Autodesk Fusion 360 part; units mm, degrees
(part 2 of 2)
sketch "Logo" plane through (0, 0, 0) normal (0, 1, 0) x (1, 0, 0)
  line L0 (160, 0) -> (201, 0)
  line L1 (201, 0) -> (201, 7)
  line L2 (201, 7) -> (160, 7)
  line L3 (160, 7) -> (160, 0)
  line L4 (196.0195, -0.004) -> (196.0195, 0.9966)
  line L5 (196.0195, 0.9966) -> (201.0223, 0.9966)
  line L6 (201.0223, 0.9966) -> (201.0223, -0.004)
  line L7 (201.0223, -0.004) -> (196.0195, -0.004)
  line L8 (196.0195, 6.9998) -> (201.0223, 6.9998)
  line L9 (201.0223, 6.9998) -> (201.0223, 5.9993)
  line L10 (201.0223, 5.9993) -> (196.0195, 5.9993)
  line L11 (196.0195, 5.9993) -> (196.0195, 6.9998)
  line L12 (191.0168, 0.9966) -> (194.0184, 0.9966)
  line L13 (194.0184, 0.9966) -> (194.0184, -0.004)
  line L14 (194.0184, -0.004) -> (191.0168, -0.004)
  line L15 (191.0168, -0.004) -> (191.0168, 0.9966)
  line L16 (190.0163, 5.9993) -> (191.0168, 5.9993)
  line L17 (191.0168, 5.9993) -> (191.0168, 0.9966)
  line L18 (191.0168, 0.9966) -> (190.0163, 0.9966)
  line L19 (190.0163, 0.9966) -> (190.0163, 5.9993)
  line L20 (194.0184, 6.9998) -> (194.0184, 5.9993)
  line L21 (194.0184, 5.9993) -> (191.0168, 5.9993)
  line L22 (191.0168, 5.9993) -> (191.0168, 6.9998)
  line L23 (191.0168, 6.9998) -> (194.0184, 6.9998)
  line L24 (186.0141, -0.004) -> (185.0135, -0.004)
  line L25 (185.0135, -0.004) -> (185.0135, 0.9966)
  line L26 (185.0135, 0.9966) -> (186.0141, 0.9966)
  line L27 (186.0141, 0.9966) -> (186.0141, 4.9987)
  line L28 (186.0141, 4.9987) -> (187.0146, 4.9987)
  line L29 (187.0146, 4.9987) -> (187.0146, 0.9966)
  line L30 (187.0146, 0.9966) -> (188.0152, 0.9966)
  line L31 (188.0152, 0.9966) -> (188.0152, -0.004)
  line L32 (188.0152, -0.004) -> (186.0141, -0.004)
  line L33 (185.0135, 6.9998) -> (188.0152, 6.9998)
  line L34 (188.0152, 6.9998) -> (188.0152, 5.9993)
  line L35 (188.0152, 5.9993) -> (185.0135, 5.9993)
  line L36 (185.0135, 5.9993) -> (185.0135, 6.9998)
  line L37 (179.0103, -0.004) -> (178.0097, -0.004)
  line L38 (178.0097, -0.004) -> (178.0097, 4.9987)
  line L39 (178.0097, 4.9987) -> (179.0103, 4.9987)
  line L40 (179.0103, 4.9987) -> (179.0103, 0.9966)
  line L41 (179.0103, 0.9966) -> (182.0119, 0.9966)
  line L42 (182.0119, 0.9966) -> (182.0119, -0.004)
  line L43 (182.0119, -0.004) -> (179.0103, -0.004)
  line L44 (182.0119, 5.9993) -> (183.0124, 5.9993)
  line L45 (183.0124, 5.9993) -> (183.0124, 0.9966)
  line L46 (183.0124, 0.9966) -> (182.0119, 0.9966)
  line L47 (182.0119, 0.9966) -> (182.0119, 5.9993)
  line L48 (178.0097, 6.9998) -> (182.0119, 6.9998)
  line L49 (182.0119, 6.9998) -> (182.0119, 5.9993)
  line L50 (182.0119, 5.9993) -> (178.0097, 5.9993)
  line L51 (178.0097, 5.9993) -> (178.0097, 6.9998)
  line L52 (172.0064, 0.9966) -> (177.0092, 0.9966)
  line L53 (177.0092, 0.9966) -> (177.0092, -0.004)
  line L54 (177.0092, -0.004) -> (172.0064, -0.004)
  line L55 (172.0064, -0.004) -> (172.0064, 0.9966)
  line L56 (170.0054, 4.9987) -> (171.0059, 4.9987)
  line L57 (171.0059, 4.9987) -> (171.0059, 0.9966)
  line L58 (171.0059, 0.9966) -> (170.0054, 0.9966)
  line L59 (170.0054, 0.9966) -> (170.0054, 4.9987)
  line L60 (170.0054, -0.004) -> (167.0037, -0.004)
  line L61 (167.0037, -0.004) -> (167.0037, 0.9966)
  line L62 (167.0037, 0.9966) -> (170.0054, 0.9966)
  line L63 (170.0054, 0.9966) -> (170.0054, -0.004)
  line L64 (166.0032, 0.9966) -> (166.0032, 4.9987)
  line L65 (166.0032, 4.9987) -> (167.0037, 4.9987)
  line L66 (167.0037, 4.9987) -> (167.0037, 0.9966)
  line L67 (167.0037, 0.9966) -> (166.0032, 0.9966)
  line L68 (167.0037, 5.9993) -> (170.0054, 5.9993)
  line L69 (170.0054, 5.9993) -> (170.0054, 4.9987)
  line L70 (170.0054, 4.9987) -> (167.0037, 4.9987)
  line L71 (167.0037, 4.9987) -> (167.0037, 5.9993)
  line L72 (164.0021, 4.9987) -> (165.0026, 4.9987)
  line L73 (165.0026, 4.9987) -> (165.0026, -0.004)
  line L74 (165.0026, -0.004) -> (164.0021, -0.004)
  line L75 (164.0021, -0.004) -> (164.0021, 4.9987)
  line L76 (161.0004, -0.004) -> (159.9999, -0.004)
  line L77 (159.9999, -0.004) -> (159.9999, 5.9993)
  line L78 (159.9999, 5.9993) -> (164.0021, 5.9993)
  line L79 (164.0021, 5.9993) -> (164.0021, 4.9987)
  line L80 (164.0021, 4.9987) -> (161.0004, 4.9987)
  line L81 (161.0004, 4.9987) -> (161.0004, -0.004)
  line L82 (200.0217, 2.9977) -> (196.0195, 2.9977)
  line L83 (196.0195, 2.9977) -> (196.0195, 3.9982)
  line L84 (196.0195, 3.9982) -> (200.0217, 3.9982)
  line L85 (200.0217, 3.9982) -> (200.0217, 2.9977)
  line L86 (160, 10) -> (180.5, 10)
  line L87 (180.5, 10) -> (180.5, 13.5)
  line L88 (180.5, 13.5) -> (160, 13.5)
  line L89 (160, 13.5) -> (160, 10)
  line L90 (177.9981, 9.9995) -> (177.9981, 10.4994)
  line L91 (177.9981, 10.4994) -> (180.4979, 10.4994)
  line L92 (180.4979, 10.4994) -> (180.4979, 9.9995)
  line L93 (180.4979, 9.9995) -> (177.9981, 9.9995)
  line L94 (177.9981, 13.4992) -> (180.4979, 13.4992)
  line L95 (180.4979, 13.4992) -> (180.4979, 12.9993)
  line L96 (180.4979, 12.9993) -> (177.9981, 12.9993)
  line L97 (177.9981, 12.9993) -> (177.9981, 13.4992)
  line L98 (175.4983, 10.4994) -> (176.9982, 10.4994)
  line L99 (176.9982, 10.4994) -> (176.9982, 9.9995)
  line L100 (176.9982, 9.9995) -> (175.4983, 9.9995)
  line L101 (175.4983, 9.9995) -> (175.4983, 10.4994)
  line L102 (174.9984, 12.9993) -> (175.4983, 12.9993)
  line L103 (175.4983, 12.9993) -> (175.4983, 10.4994)
  line L104 (175.4983, 10.4994) -> (174.9984, 10.4994)
  line L105 (174.9984, 10.4994) -> (174.9984, 12.9993)
  line L106 (176.9982, 13.4992) -> (176.9982, 12.9993)
  line L107 (176.9982, 12.9993) -> (175.4983, 12.9993)
  line L108 (175.4983, 12.9993) -> (175.4983, 13.4992)
  line L109 (175.4983, 13.4992) -> (176.9982, 13.4992)
  line L110 (172.9985, 9.9995) -> (172.4985, 9.9995)
  line L111 (172.4985, 9.9995) -> (172.4985, 10.4994)
  line L112 (172.4985, 10.4994) -> (172.9985, 10.4994)
  line L113 (172.9985, 10.4994) -> (172.9985, 12.4993)
  line L114 (172.9985, 12.4993) -> (173.4985, 12.4993)
  line L115 (173.4985, 12.4993) -> (173.4985, 10.4994)
  line L116 (173.4985, 10.4994) -> (173.9984, 10.4994)
  line L117 (173.9984, 10.4994) -> (173.9984, 9.9995)
  line L118 (173.9984, 9.9995) -> (172.9985, 9.9995)
  line L119 (172.4985, 13.4992) -> (173.9984, 13.4992)
  line L120 (173.9984, 13.4992) -> (173.9984, 12.9993)
  line L121 (173.9984, 12.9993) -> (172.4985, 12.9993)
  line L122 (172.4985, 12.9993) -> (172.4985, 13.4992)
  line L123 (169.4988, 9.9995) -> (168.9988, 9.9995)
  line L124 (168.9988, 9.9995) -> (168.9988, 12.4993)
  line L125 (168.9988, 12.4993) -> (169.4988, 12.4993)
  line L126 (169.4988, 12.4993) -> (169.4988, 10.4994)
  line L127 (169.4988, 10.4994) -> (170.9987, 10.4994)
  line L128 (170.9987, 10.4994) -> (170.9987, 9.9995)
  line L129 (170.9987, 9.9995) -> (169.4988, 9.9995)
  line L130 (170.9987, 12.9993) -> (171.4986, 12.9993)
  line L131 (171.4986, 12.9993) -> (171.4986, 10.4994)
  line L132 (171.4986, 10.4994) -> (170.9987, 10.4994)
  line L133 (170.9987, 10.4994) -> (170.9987, 12.9993)
  line L134 (168.9988, 13.4992) -> (170.9987, 13.4992)
  line L135 (170.9987, 13.4992) -> (170.9987, 12.9993)
  line L136 (170.9987, 12.9993) -> (168.9988, 12.9993)
  line L137 (168.9988, 12.9993) -> (168.9988, 13.4992)
  line L138 (165.999, 10.4994) -> (168.4988, 10.4994)
  line L139 (168.4988, 10.4994) -> (168.4988, 9.9995)
  line L140 (168.4988, 9.9995) -> (165.999, 9.9995)
  line L141 (165.999, 9.9995) -> (165.999, 10.4994)
  line L142 (164.9991, 12.4993) -> (165.4991, 12.4993)
  line L143 (165.4991, 12.4993) -> (165.4991, 10.4994)
  line L144 (165.4991, 10.4994) -> (164.9991, 10.4994)
  line L145 (164.9991, 10.4994) -> (164.9991, 12.4993)
  line L146 (164.9991, 9.9995) -> (163.4992, 9.9995)
  line L147 (163.4992, 9.9995) -> (163.4992, 10.4994)
  line L148 (163.4992, 10.4994) -> (164.9991, 10.4994)
  line L149 (164.9991, 10.4994) -> (164.9991, 9.9995)
  line L150 (162.9992, 10.4994) -> (162.9992, 12.4993)
  line L151 (162.9992, 12.4993) -> (163.4992, 12.4993)
  line L152 (163.4992, 12.4993) -> (163.4992, 10.4994)
  line L153 (163.4992, 10.4994) -> (162.9992, 10.4994)
  line L154 (163.4992, 12.9993) -> (164.9991, 12.9993)
  line L155 (164.9991, 12.9993) -> (164.9991, 12.4993)
  line L156 (164.9991, 12.4993) -> (163.4992, 12.4993)
  line L157 (163.4992, 12.4993) -> (163.4992, 12.9993)
  line L158 (161.9993, 12.4993) -> (162.4993, 12.4993)
  line L159 (162.4993, 12.4993) -> (162.4993, 9.9995)
  line L160 (162.4993, 9.9995) -> (161.9993, 9.9995)
  line L161 (161.9993, 9.9995) -> (161.9993, 12.4993)
  line L162 (160.4994, 9.9995) -> (159.9995, 9.9995)
  line L163 (159.9995, 9.9995) -> (159.9995, 12.9993)
  line L164 (159.9995, 12.9993) -> (161.9993, 12.9993)
  line L165 (161.9993, 12.9993) -> (161.9993, 12.4993)
  line L166 (161.9993, 12.4993) -> (160.4994, 12.4993)
  line L167 (160.4994, 12.4993) -> (160.4994, 9.9995)
  line L168 (179.998, 11.4994) -> (177.9981, 11.4994)
  line L169 (177.9981, 11.4994) -> (177.9981, 11.9993)
  line L170 (177.9981, 11.9993) -> (179.998, 11.9993)
  line L171 (179.998, 11.9993) -> (179.998, 11.4994)
  dimension "d388" = 41
  dimension "d389" = 7
  dimension "d390" = 20.5
  dimension "d391" = 3.5
  constraint horizontal L0
  constraint vertical L1
  constraint horizontal L2
  constraint vertical L3
  constraint horizontal L86
  constraint vertical L87
  constraint horizontal L88
  constraint vertical L89
  measures "d388" distance of L0.start L0.end
  measures "d389" distance of L0.start L2.end
  measures "d390" distance of L86.start L86.end
  measures "d391" distance of L86.start L88.end
extrude "Extrude42" add sketch "Logo" along normal blind 0.4 separate body contours L86 L89 L162 L163 L164 L165 L166 L167 | L86 L161 L166 L167 | L86 L88 L89 L124 L125 L126 L127 L133 L136 L137 L138 L139 L141 L142 L143 L144 L147 L149 L150 L151 L153 L154 L155 L157 L158 L159 L164 L165 | L86 L158 L159 L160 L161 | L88 L134 L135 L136 L137 | L86 L146 L147 L148 L149 | L86 L88 L101 L102 L104 L105 L108 L111 L112 L113 L114 L115 L116 L117 L120 L121 L122 L128 L130 L131 L132 L135 | L145 L148 L152 L156 | L150 L151 L152 L153 | L88 L119 L120 L121 L122 | L130 L131 L132 L133 | L86 L138 L139 L140 L141 | L142 L143 L144 L145 | L154 L155 L156 L157 | L86 L123 L124 L125 L126 L127 L128 L129 | L88 L106 L107 L108 L109 | L88 L94 L95 L96 L97 | L86 L87 L88 L90 L91 L92 L95 L96 L97 L98 L99 L103 L106 L107 | L102 L103 L104 L105 | L86 L110 L111 L112 L113 L114 L115 L116 L117 L118 | L86 L98 L99 L100 L101 | L86 L90 L91 L92 L93 | L168 L169 L170 L171 makes body 7
extrude "Extrude43" add sketch "Logo" along normal blind 1 contours L86 L89 L162 L163 L164 L165 L166 L167 | L86 L158 L159 L160 L161 | L88 L134 L135 L136 L137 | L86 L146 L147 L148 L149 | L150 L151 L152 L153 | L88 L119 L120 L121 L122 | L130 L131 L132 L133 | L86 L138 L139 L140 L141 | L142 L143 L144 L145 | L154 L155 L156 L157 | L86 L123 L124 L125 L126 L127 L128 L129 | L88 L106 L107 L108 L109 | L88 L94 L95 L96 L97 | L102 L103 L104 L105 | L86 L110 L111 L112 L113 L114 L115 L116 L117 L118 | L86 L98 L99 L100 L101 | L86 L90 L91 L92 L93 | L168 L169 L170 L171 bodies 7
extrude "Extrude44" add sketch "Side" along normal blind 2.8 contours L78 L79 L80 L81 bodies 6
sketch "Spacer" plane through (0, 0, 0) normal (0, 1, 0) x (1, 0, 0)
  line L0 (220, 0) -> (245.6, 0)
  line L1 (245.6, 0) -> (245.6, 19)
  line L2 (245.6, 19) -> (220, 19)
  line L3 (220, 19) -> (220, 0)
  line L4 (227.8, 0) -> (237.8, 0)
  line L5 (237.8, 0) -> (237.8, 10)
  line L6 (237.8, 10) -> (227.8, 10)
  line L7 (227.8, 10) -> (227.8, 0)
  line L8 (220.8, 0) -> (221.8, 0)
  line L9 (221.8, 0) -> (221.8, 19)
  line L10 (221.8, 19) -> (220.8, 19)
  line L11 (220.8, 19) -> (220.8, 0)
  line L12 (244.8, 0) -> (243.8, 0)
  line L13 (243.8, 0) -> (243.8, 19)
  line L14 (243.8, 19) -> (244.8, 19)
  line L15 (244.8, 19) -> (244.8, 0)
  dimension "d402" = 25.6
  dimension "d403" = 19
  dimension "d406" = 10
  dimension "d407" = 10
  dimension "d408" = 7.8
  dimension "d413" = 1
  dimension "d414" = 19
  dimension "d415" = 0.8
  dimension "d416" = 1
  dimension "d417" = 19
  dimension "d418" = 0.8
  constraint horizontal L0
  constraint vertical L1
  constraint horizontal L2
  constraint vertical L3
  constraint horizontal L4
  constraint vertical L5
  constraint horizontal L6
  constraint vertical L7
  constraint coincident L0 L4.start
  constraint horizontal L8
  constraint vertical L9
  constraint horizontal L10
  constraint vertical L11
  constraint coincident L0 L8.start
  constraint horizontal L12
  constraint vertical L13
  constraint horizontal L14
  constraint vertical L15
  constraint coincident L0 L12.start
  measures "d402" distance of L0.start L0.end
  measures "d403" distance of L0.start L2.end
  measures "d406" distance of L4.start L4.end
  measures "d407" distance of L4.start L6.end
  measures "d408" distance of L3 L7
  measures "d413" distance of L8.start L8.end
  measures "d414" distance of L8.start L10.end
  measures "d415" distance of L3 L11
  measures "d416" distance of L12.start L12.end
  measures "d417" distance of L12.start L14.end
  measures "d418" distance of L1 L15
extrude "Extrude47" add sketch "Spacer" along normal blind 2 separate body contours L0 L2 L3 L11 | L0 L2 L8 L9 L10 L11 | L0 L2 L5 L6 L7 L9 L13 | L0 L2 L12 L13 L14 L15 | L0 L1 L2 L15 makes body 8
extrude "Extrude48" add sketch "Spacer" along normal blind 7 contours L0 L2 L8 L9 L10 L11 | L0 L2 L12 L13 L14 L15 bodies 8
extrude "Extrude49" cut sketch "Side IO" along normal blind 1 contours A4 bodies 2
extrude "Extrude50" cut sketch "Frame" along normal blind 60 contours A0 | A1 | A2 | A3 bodies 1
extrude "Extrude51" add sketch "Frame" along normal blind 56 contours A0 | A1 | A2 | A3 bodies 1
extrude "Extrude52" cut sketch "Side" along normal blind 1 contours A2 | A3 bodies 6
fillet "Fillet11" radius 0.6 4 edges at (0.994, 56, -30.2351) (29.794, 56, -30.2351) (29.394, 56, -2.2351) (1.394, 56, -2.2351) on bodies 1
extrude "Extrude54" cut sketch "Frame" along normal blind 4 contours L59 L69 A4 | L58 L69 A4 | L58 L59 A4 | L62 L70 A5 | L63 L70 A5 | L62 L63 A5 | A2 | A3 bodies 1
fillet "Fillet14" radius 0.6 4 edges at (29.394, 4, -1.7649) (1.394, 4, -1.7649) (1.394, 4, -36.7649) (29.394, 4, -36.7649) on bodies 1
chamfer "Chamfer2" distance 0.8 angle 45 2 edges at (4.5, 10, -36) (27.5, 10, -36) tangent chain off on bodies 1
named bodies: "Frame", "Side IO", "Switch Handle (exp)", "Top", "Switch Skirt", "Side", "Logo", "Spacer"
